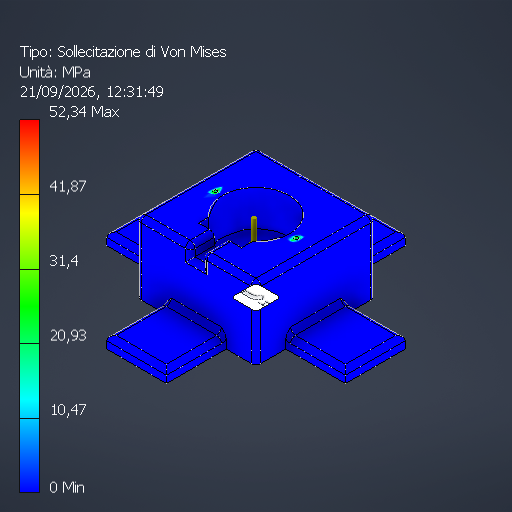
# Autodesk Inventor part: Base
Saved by Autodesk Inventor 2026.1 (Build 301233020, 233B)
## iProperties
Created: 2026-09-20
Part Number: Base
Material: Generico
Document SubType Name: Modeling
Designer: nuzzo
Density: 1 g/cm^3
Appearance: Default
Mass: 76.886 g
Surface Area: 181.198 cm^2
Volume: 76.886 cm^3
Author: nuzzo
Autodesk Inventor part; units mm, degrees
ref_plane "YZ Plane" through (0, 0, 0) normal (1, 0, 0) x (0, 1, 0)
ref_plane "XZ Plane" through (0, 0, 0) normal (0, 1, 0) x (-1, 0, 0)
ref_plane "XY Plane" through (0, 0, 0) normal (0, 0, 1) x (1, 0, 0)
sketch "Schizzo1" plane through (0, 0, 0) normal (0, 1, 0) x (-1, 0, 0)
  line L0 (25, 25) -> (-25, 25)
  line L1 (-25, 25) -> (-25, -25)
  line L2 (-25, -25) -> (25, -25)
  line L3 (25, -25) -> (25, 25)
  line L4 (25, 25) -> (-25, -25) construction
  line L5 (-25, 25) -> (25, -25) construction
  line L6 (50, 12.5) -> (-50, 12.5)
  line L7 (-50, 12.5) -> (-50, -12.5)
  line L8 (-50, -12.5) -> (50, -12.5)
  line L9 (50, -12.5) -> (50, 12.5)
  line L10 (50, 12.5) -> (-50, -12.5) construction
  line L11 (-50, 12.5) -> (50, -12.5) construction
  line L12 (12.5, 50) -> (-12.5, 50)
  line L13 (-12.5, 50) -> (-12.5, -50)
  line L14 (-12.5, -50) -> (12.5, -50)
  line L15 (12.5, -50) -> (12.5, 50)
  line L16 (12.5, 50) -> (-12.5, -50) construction
  line L17 (-12.5, 50) -> (12.5, -50) construction
  point P0 (0, 0)
  point P1 (-12.5, 25)
  point P2 (12.5, 25)
  point P3 (-25, -12.5)
  point P4 (-25, 12.5)
  point P5 (25, 12.5)
  point P6 (25, -12.5)
  point P7 (12.5, -25)
  point P8 (-12.5, -25)
  dimension "d0" = 50
  dimension "d1" = 50
  dimension "d2" = 100
  dimension "d3" = 25
  dimension "d4" = 25
  dimension "d5" = 100
  constraints: 36 end point, 6 midpoint, 6 parallel, 3 horizontal, 3 perpendicular
  measures "d0" distance of L2.end L1.end
  measures "d1" distance of L1.end L0.end
  measures "d2" distance of L8.end L7.end
  measures "d3" distance of L7.end L6.end
  measures "d4" distance of L14.end L13.end
  measures "d5" distance of L13.end L12.end
extrude "Estrusione1" add sketch "Schizzo1" along normal blind 30 contours L3 L6 L15 L0 | L15 L6 L13 L0 | L3 L8 L15 L6 | L13 L6 L1 L0 | L15 L8 L13 L6 | L3 L2 L15 L8 | L13 L8 L1 L6 | L15 L2 L13 L8 | L13 L2 L1 L8
extrude "Estrusione2" add sketch "Schizzo1" along normal blind 5 contours L0 L13 L12 L15 | L6 L9 L8 L3 | L1 L8 L7 L6 | L15 L14 L13 L2
sketch "Schizzo2" plane through (0, 30, 0) normal (0, 1, 0) x (1, 0, 0)
  line L0 (-25, 25) -> (-25, 12.5) projected
  line L1 (-25, -25) -> (25, -25) projected
  line L2 (25, -25) -> (-25, -25)
  line L3 (25, 25) -> (-25, 25) projected
  circle A0 centre (0, 0) radius 14
  line L4 (-9, -15) -> (9, -15)
  line L5 (9, -15) -> (9, 15)
  line L6 (9, 15) -> (-9, 15)
  line L7 (-9, 15) -> (-9, -15)
  line L8 (-9, -15) -> (9, 15) construction
  line L9 (9, -15) -> (-9, 15) construction
  line L10 (-2.5, 25) -> (2.5, 25)
  line L11 (2.5, 25) -> (2.5, -25)
  line L12 (2.5, -25) -> (-2.5, -25)
  line L13 (-2.5, -25) -> (-2.5, 25)
  line L14 (-2.5, 25) -> (2.5, -25) construction
  line L15 (2.5, 25) -> (-2.5, -25) construction
  point P0 (-9, -10.7238)
  point P1 (9, -10.7238)
  point P2 (-2.5, -15)
  point P3 (2.5, -15)
  dimension "d10" = 28
  dimension "d11" = 18
  dimension "d12" = 30
  dimension "d13" = 5
  constraints: 26 end point, 5 equal length, 4 midpoint, 2 horizontal, 2 perpendicular, 1 centre point, 1 coincident, 1 point on line
  measures "d10" diameter of A0
  measures "d11" distance of L6.end L5.end
  measures "d12" distance of L5.end L4.end
  measures "d13" distance of L11.end L12.end
extrude "Estrusione3" cut sketch "Schizzo2" against normal blind 15 contours L13 A0 L11 L4 | L4 L7 A0 L13 | L11 A0 L5 L4 | L13 A0 L11 | A0 L7 L13 | L11 A0 L5 | A0 L7 | L5 A0
extrude "Estrusione4" cut sketch "Schizzo2" against normal blind 5 contours L13 L4 L11 L1
sketch "Schizzo3" plane through (0, 30, 0) normal (0, 1, 0) x (1, 0, 0)
  line L0 (-17, -2.5) -> (17, -2.5)
  line L1 (17, -2.5) -> (17, 2.5)
  line L2 (17, 2.5) -> (-17, 2.5)
  line L3 (-17, 2.5) -> (-17, -2.5)
  line L4 (-17, -2.5) -> (17, 2.5) construction
  line L5 (17, -2.5) -> (-17, 2.5) construction
  circle A0 centre (-17, 0) radius 2.5
  circle A1 centre (17, 0) radius 2.5
  point P0 (0, 0)
  dimension "d18" = 34
  dimension "d19" = 5
  dimension "d20" = 5
  dimension "d21" = 5
  constraints: 12 end point, 4 midpoint, 2 centre point, 2 parallel, 1 horizontal, 1 perpendicular
  measures "d18" distance of L2.end L1.end
  measures "d19" distance of L1.end L0.end
  measures "d20" diameter of A0
  measures "d21" diameter of A1
hole "Foro1" at (-17, 30, 0) at (17, 30, 0) direction (0, -1, 0) diameter 1.567 end through all thread size "M2x0.4" class "6H" standard "ISO Metric profile"
fillet "Raccordo1" radius 2 30 edges at (25, 30, 0) (-25, 30, 0) (-13.75, 30, 25) (13.75, 30, 25) (-2.5, 30, 20) (2.5, 30, 20) (0, 25, 25) (-2.5, 27.5, 25) (2.5, 27.5, 25) (0, 30, -25) (0, 5, 50) (-12.5, 5, 37.5) (12.5, 5, 37.5) (0, 5, 25) (25, 5, 0) (37.5, 5, 12.5) (37.5, 5, -12.5) (50, 5, 0) (-37.5, 5, -12.5) (-50, 5, 0) (-37.5, 5, 12.5) (-25, 5, 0) (0, 5, -50) (12.5, 5, -37.5) (-12.5, 5, -37.5) (0, 5, -25) (-25, 15, 25) (25, 15, 25) (25, 15, -25) (-25, 15, -25)
